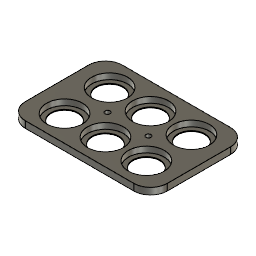
Battery holder (Autodesk Fusion 360 design; units mm, degrees)
Autodesk Fusion 360 part; units mm, degrees
sketch "Sketch1" plane through (0, 0, 0) normal (0, 0, 1) x (1, 0, 0)
  line L0 (0, 0) -> (81, 0)
  line L1 (81, 0) -> (81, 54)
  line L2 (81, 54) -> (0, 54)
  line L3 (0, 54) -> (0, 0)
  dimension "d1" = 81
  dimension "d2" = 54
  constraint horizontal L0
  constraint vertical L1
  constraint horizontal L2
  constraint vertical L3
  constraint coincident L0.start L3.end
  measures "d1" distance of L0.start L0.end
  measures "d2" distance of L0.start L2.end
sketch "Sketch2" plane through (0, 0, 0) normal (0, 0, 1) x (1, 0, 0)
extrude "Extrude1" add sketch "Sketch1" along normal blind 4
sketch "Sketch3" plane through (0, 0, 4) normal (0, 0, 1) x (-1, 0, 0)
  line L0 (0, -54) -> (0, 0)
  line L1 (0, 0) -> (-81, 0)
  line L2 (-81, 0) -> (-81, -54)
  line L3 (-81, -54) -> (0, -54)
  line L4 (0, -27) -> (-81, -27)
  line L5 (0, -27) -> (0, -40.5)
  line L6 (0, -40.5) -> (-81, -40.5)
  line L7 (0, -27) -> (0, -13.5)
  line L8 (0, -13.5) -> (-81, -13.5)
  line L9 (-40.5, -54) -> (-40.5, 0)
  circle A0 centre (-40.5, -40.5) radius 10.75
  circle A1 centre (-40.5, -13.5) radius 10.75
  line L10 (-40.5, -40.5) -> (-65, -40.5)
  circle A2 centre (-65, -40.5) radius 10.75
  circle A3 centre (-65, -13.5) radius 10.75
  line L11 (-40.5, -40.5) -> (-16, -40.5)
  circle A4 centre (-16, -40.5) radius 10.75
  circle A5 centre (-16, -13.5) radius 10.75
  dimension "d5" = 13.5
  dimension "d6" = 13.5
  dimension "d7" = 21.5
  dimension "d8" = 21.5
  dimension "d9" = 24.5
  dimension "d10" = 21.5
  dimension "d11" = 21.5
  dimension "d12" = 24.5
  dimension "d13" = 21.5
  dimension "d14" = 21.5
  constraint midpoint L0 L4.start
  constraint midpoint L2 L4.end
  constraint perpendicular L3 L5
  constraint coincident L2 L6.end
  constraint perpendicular L2 L6
  constraint perpendicular L4 L7
  constraint coincident L2 L8.end
  constraint perpendicular L2 L8
  constraint midpoint L3 L9.start
  constraint midpoint L1 L9.end
  constraint midpoint L6 A0.centre
  constraint midpoint L8 A1.centre
  constraint coincident A0.centre L10.start
  constraint perpendicular L2 L10
  constraint coincident L10.end A2.centre
  constraint coincident L8 A3.centre
  constraint parallel L6 L11
  constraint coincident L11.end A4.centre
  constraint coincident L8 A5.centre
  measures "d5" distance of L4.start L5.end
  measures "d6" distance of L4.start L7.end
  measures "d7" diameter of A0
  measures "d8" diameter of A1
  measures "d9" distance of A0.centre L10.end
  measures "d10" diameter of A2
  measures "d11" diameter of A3
  measures "d12" distance of A0.centre L11.end
  measures "d13" diameter of A4
  measures "d14" diameter of A5
sketch "Sketch4" plane through (0, 0, 4) normal (0, 0, 1) x (-1, 0, 0)
  circle A0 centre (-16, -40.5) radius 8
  circle A1 centre (-40.5, -40.5) radius 8
  circle A2 centre (-65, -40.5) radius 8
  circle A3 centre (-16, -13.5) radius 8
  circle A4 centre (-40.5, -13.5) radius 8
  circle A5 centre (-65, -13.5) radius 8
  dimension "d15" = 16
  dimension "d16" = 16
  dimension "d17" = 16
  dimension "d18" = 16
  dimension "d19" = 16
  dimension "d20" = 16
  measures "d15" diameter of A0
  measures "d16" diameter of A1
  measures "d17" diameter of A2
  measures "d18" diameter of A3
  measures "d19" diameter of A4
  measures "d20" diameter of A5
extrude "Extrude2" cut sketch "Sketch4" against normal blind 100
extrude "Extrude3" cut sketch "Sketch3" against normal blind 3.5 contours L6 L11 A4 | L6 L11 A4 | L6 L9 A0 L10 | L6 L9 A0 L11 | L6 L9 A0 L11 | L6 L9 A0 L10 | L8 A5 | L8 A5 | L8 L9 A1 | L8 L9 A1 | L6 L10 A2 | L6 L10 A2 | L8 L9 A1 | L8 L9 A1 | L8 A3 | L8 A3
extrude "Extrude4" add 1 faces at (27, 0, 1.3333) along direction (0, -1, 0) blind 2
extrude "Extrude5" add 1 faces at (0, 16.6667, 2.6667) along direction (-1, 0, 0) blind 2
extrude "Extrude6" add 1 faces at (81, 16.6667, 2.6667) along direction (1, 0, 0) blind 2
extrude "Extrude7" add 1 faces at (54.6667, 54, 1.3333) along direction (0, 1, 0) blind 2
fillet "Fillet1" radius 10 4 edges at (83, -2, 2) (-2, -2, 2) (83, 56, 2) (-2, 56, 2)
sketch "Sketch5" plane through (0, 0, 0) normal (0, 0, -1) x (1, 0, 0)
  circle A0 centre (16, -13.5) radius 8
  circle A1 centre (16, -40.5) radius 8
  circle A2 centre (40.5, -13.5) radius 8
  circle A3 centre (65, -40.5) radius 8
  circle A4 centre (40.5, -40.5) radius 8
  circle A5 centre (65, -13.5) radius 8
  arc A6 (-2, -46) -> (8, -56) centre (8, -46) ccw
  line L0 (8, -56) -> (73, -56)
  arc A7 (73, -56) -> (83, -46) centre (73, -46) ccw
  line L1 (83, -46) -> (83, -8)
  arc A8 (83, -8) -> (73, 2) centre (73, -8) ccw
  line L2 (73, 2) -> (8, 2)
  arc A9 (8, 2) -> (-2, -8) centre (8, -8) ccw
  line L3 (-2, -8) -> (-2, -46)
  line L4 (83, -27) -> (-2, -27)
  line L5 (65, -40.5) -> (40.5, -13.5)
  line L6 (40.5, -13.5) -> (16, -40.5)
  circle A10 centre (52.75, -27) radius 1.5
  circle A11 centre (28.25, -27) radius 1.5
  dimension "d35" = 3
  dimension "d36" = 3
  constraint midpoint L1 L4.start
  constraint midpoint L3 L4.end
  constraint coincident A3.centre L5.start
  constraint coincident A2.centre L5.end
  constraint coincident A1.centre L6.end
  constraint midpoint L5 A10.centre
  constraint midpoint L6 A11.centre
  measures "d35" diameter of A10
  measures "d36" diameter of A11
sketch "Sketch6" plane through (0, 0, 0) normal (0, 0, -1) x (1, 0, 0)
extrude "Extrude8" cut sketch "Sketch5" against normal blind 187 contours L4 L6 A11 | L4 L6 A11 | L4 L5 A10 | L4 L5 A10 | L4 L6 A11 | L4 L6 A11 | L4 L5 A10 | L4 L5 A10
equation "d5 = ( 27 / 2 ) * 1 mm"
equation "d6 = ( 27 / 2 ) * 1 mm"
equation "d9 = 21.5 mm + 3 mm"
equation "d23 = -4.0 mm + 0.5 mm"
